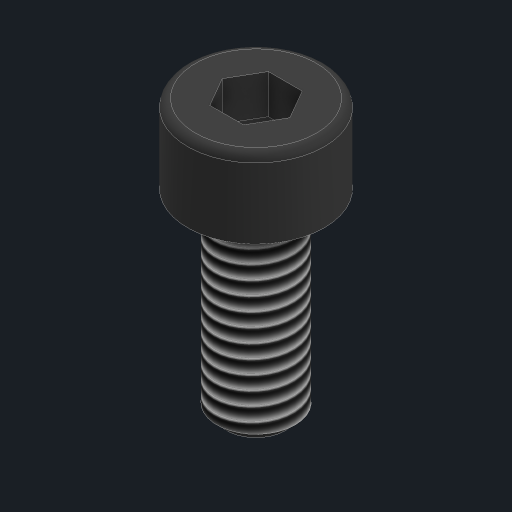
# Autodesk Inventor part: Parafuso allen cabeça cilíndrica DIN 912 M4x10
Saved by Autodesk Inventor 2024.3 (Build 283343000, 343)
## iProperties
Created: 2025-02-01
Part Number: Parafuso allen cabeça cilíndrica DIN 912 M4x10
Material: Aço, carbono
Document SubType Name: Modeling
Designer: Cliente
Density: 7.85 g/cm^3
Appearance: Aço - Polido(1)
Mass: 2.03163 g
Surface Area: 3.07188 cm^2
Volume: 0.258806 cm^3
Author: Cliente
Autodesk Inventor part; units mm, degrees
ref_plane "YZ Plane" through (0, 0, 0) normal (1, 0, 0) x (0, 1, 0)
ref_plane "XZ Plane" through (0, 0, 0) normal (0, 1, 0) x (-1, 0, 0)
ref_plane "XY Plane" through (0, 0, 0) normal (0, 0, 1) x (1, 0, 0)
sketch "Esboço1" plane through (0, 0, 0) normal (0, 0, 1) x (1, 0, 0)
  line L0 (0, 0) -> (2, 0)
  line L1 (2, -0.2) -> (2, -9.5)
  line L2 (2.2, 0) -> (3.5, 0)
  line L3 (3.5, 0) -> (3.5, 3.6)
  line L4 (3.1, 4) -> (1.7321, 4)
  line L5 (1.7321, 4) -> (1.7321, 2)
  line L6 (1.7321, 2) -> (0, 1)
  line L7 (1.7321, 2) -> (3.7321, 2) construction
  line L8 (1.5, -10) -> (0, -10)
  line L9 (0, -10) -> (0, 1)
  arc A0 (3.5, 3.6) -> (3.1, 4) centre (3.1, 3.6) ccw
  arc A1 (2.2, 0) -> (2, -0.2) centre (2.2, -0.2) ccw
  line L10 (0, 9.4882) -> (1.5, 8.6222)
  line L11 (1.5, 8.6222) -> (1.5, 6.8901)
  line L12 (1.5, 6.8901) -> (0, 6.0241)
  line L13 (0, 6.0241) -> (-1.5, 6.8901)
  line L14 (-1.5, 6.8901) -> (-1.5, 8.6222)
  line L15 (-1.5, 8.6222) -> (0, 9.4882)
  line L16 (2, -9.5) -> (1.5, -10)
  point P0 (2, -10)
  point P1 (3.5, 4)
  point P2 (0, 7.7562)
  dimension "d0" = 2
  dimension "d1" = 10
  dimension "d2" = 3.5
  dimension "d3" = 4
  dimension "d5" = 2
  dimension "d6" = 150
  dimension "d8" = 0.4
  dimension "d9" = 0.2
  dimension "d10" = 3
  dimension "d11" = 3.4641
  dimension "d12" = 3.4641
  dimension "d17" = 0.5
  dimension "d18" = 0.5
  constraints: 34 end point, 6 point on line, 5 horizontal, 4 perpendicular, 4 point on circle, 4 tangent, 2 centre point, 2 vertical alignment, 1 equal length, 13 other
  measures "d0" distance of L0.start L0.end
  measures "d1" distance of L0.end point (2, -10)
  measures "d2" distance of L0.start L2.end
  measures "d3" distance of L2.end point (3.5, 4)
  measures "d5" distance of L4.end L5.end
  measures "d6" angle of L6 L7
  measures "d8" radius of A0
  measures "d9" radius of A1
  measures "d10" distance between parallel lines of L14 L11
  measures "d11" distance of L12.end L10.start
  measures "d12" diameter of L5 L9
  measures "d17" distance of L1.end point (2, -10)
  measures "d18" distance of L8.start point (2, -10)
revolve "Revolução1" add sketch "Esboço1" angle 360 about axis through (0, -10, 0) along (0, 1, 0) contours L1 L16 L8 L9 L6 L5 L4 A0 L3 L2 A1
sketch "Esboço2" plane through (0, 4, 0) normal (0, 1, 0) x (1, 0, 0)
  circle A0 centre (0, 0) radius 1.7321 projected
  circle A1 centre (0, 0) radius 3.1 projected
  line L0 (-1.7321, 0) -> (-0.866, 1.5)
  line L1 (-0.866, 1.5) -> (0.866, 1.5)
  line L2 (0.866, 1.5) -> (1.7321, 0)
  line L3 (1.7321, 0) -> (0.866, -1.5)
  line L4 (0.866, -1.5) -> (-0.866, -1.5)
  line L5 (-0.866, -1.5) -> (-1.7321, 0)
  point P0 (0, 0)
  point P1 (0.866, -1.5)
  point P2 (0.866, -1.5)
  point P3 (1.7321, 0)
  point P4 (1.7321, 0)
  point P5 (-0.866, 1.5)
  point P6 (-0.866, 1.5)
  constraints: 12 end point, 1 coincident, 1 horizontal alignment, 15 other
extrude "Extrusão1" add sketch "Esboço2" against normal blind 2 contours L2 A0 | A0 L3 | L1 A0 | A0 L4 | L0 A0 | A0 L5
thread "Rosca1" size "M4x0.7" class "6g" standard "ANSI Metric M Profile" full length
equation "\"d18\" = d17"
